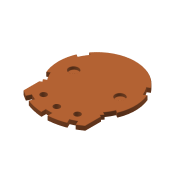
# Autodesk Inventor part: base
Saved by Autodesk Inventor 2015 SP1 (Build 190203100, 203)
## iProperties
Created: 2015-06-21
Part Number: base
Material: Generic
Document SubType Name: Modeling
Designer: Peter Mulkers
Density: 1 g/cm^3
Appearance: Orange
Author: Peter Mulkers
Autodesk Inventor part; units mm, degrees
ref_plane "YZ Plane" through (0, 0, 0) normal (1, 0, 0) x (0, 1, 0)
ref_plane "XZ Plane" through (0, 0, 0) normal (0, 1, 0) x (-1, 0, 0)
ref_plane "XY Plane" through (0, 0, 0) normal (0, 0, 1) x (1, 0, 0)
sketch "Sketch1" plane through (0, 0, 0) normal (0, 0, 1) x (1, 0, 0)
  line L0 (0, 0) -> (0, 12.5) construction
  line L1 (0, 0) -> (-10.8253, 6.25) construction
  line L2 (0, 0) -> (-10.8253, -6.25) construction
  line L3 (0, 0) -> (0, -12.5) construction
  line L4 (0, 0) -> (10.8253, -6.25) construction
  line L5 (0, 0) -> (10.8253, 6.25) construction
  line L6 (-9.9971, 7.5039) -> (-9.1242, 6.9999)
  line L7 (-11.4971, 4.9058) -> (-10.6242, 4.4018)
  line L8 (9.9971, 7.5039) -> (9.1242, 6.9999)
  line L9 (11.4971, 4.9058) -> (10.6242, 4.4018)
  arc A0 (9.9971, 7.5039) -> (-9.9971, 7.5039) centre (0, 0) ccw
  line L10 (-17.5, 0) -> (17.5, 0) construction
  line L11 (-9.9971, -7.5039) -> (-9.1242, -6.9999)
  line L12 (-11.4971, -4.9058) -> (-10.6242, -4.4018)
  line L13 (9.9971, -7.5039) -> (9.1242, -6.9999)
  line L14 (11.4971, -4.9058) -> (10.6242, -4.4018)
  arc A1 (-11.4971, 4.9058) -> (-11.4971, -4.9058) centre (0, 0) ccw
  arc A2 (11.4971, -4.9058) -> (11.4971, 4.9058) centre (0, 0) ccw
  line L15 (-10, -8.6603) -> (-10, -13.7477)
  line L16 (-9.3566, -8.2888) -> (-10, -8.6603)
  line L17 (10, -8.6603) -> (10, -13.7477)
  line L18 (9.3566, -8.2888) -> (10, -8.6603)
  arc A3 (-9.9971, -7.5039) -> (-9.3566, -8.2888) centre (0, 0) ccw
  arc A4 (9.3566, -8.2888) -> (9.9971, -7.5039) centre (0, 0) ccw
  arc A5 (-9.1242, 6.9999) -> (-10.6242, 4.4018) centre (0, 0) ccw
  arc A6 (-10.6242, -4.4018) -> (-9.1242, -6.9999) centre (0, 0) ccw
  arc A7 (9.1242, -6.9999) -> (10.6242, -4.4018) centre (0, 0) ccw
  arc A8 (10.6242, 4.4018) -> (9.1242, 6.9999) centre (0, 0) ccw
  arc A9 (-10, -8.3066) -> (10, -8.3066) centre (0, 0) ccw construction
  line L19 (0, 0) -> (-7.1845, -15.4072) construction
  line L20 (0, 0) -> (7.1845, -15.4072) construction
  circle A10 centre (-5.494, -11.782) radius 1
  circle A11 centre (0, -13) radius 1
  circle A12 centre (5.494, -11.782) radius 1
  line L21 (-7.4432, -13.5959) -> (-8.0784, -14.9579)
  line L22 (5.6306, -14.4411) -> (6.2658, -15.8032)
  line L23 (-1, -15.4677) -> (-1, -16.9706)
  line L24 (-5.6306, -14.4411) -> (-6.2658, -15.8032)
  line L25 (1, -15.4677) -> (1, -16.9706)
  line L26 (7.4432, -13.5959) -> (8.0784, -14.9579)
  arc A13 (-7.4432, -13.5959) -> (-5.6306, -14.4411) centre (0, 0) ccw
  arc A14 (-1, -15.4677) -> (1, -15.4677) centre (0, 0) ccw
  arc A15 (5.6306, -14.4411) -> (7.4432, -13.5959) centre (0, 0) ccw
  arc A16 (-10, -13.7477) -> (-8.0784, -14.9579) centre (0, 0) ccw
  arc A17 (-6.2658, -15.8032) -> (-1, -16.9706) centre (0, 0) ccw
  arc A18 (1, -16.9706) -> (6.2658, -15.8032) centre (0, 0) ccw
  arc A19 (8.0784, -14.9579) -> (10, -13.7477) centre (0, 0) ccw
  dimension "d7" = 360
  dimension "d12" = 3
  dimension "d13" = 12.5
  dimension "d14" = 10
  dimension "d16" = 1
  dimension "d19" = 11.5
  dimension "d21" = 25
  dimension "d22" = 25
  dimension "d23" = 2
  dimension "d24" = 2
  dimension "d25" = 2
  dimension "d27" = 1
  dimension "d28" = 1
  dimension "d29" = 1
  dimension "d30" = 15.5
  dimension "d31" = 15.5
  dimension "d32" = 15.5
  dimension "d33" = 17
  dimension "d34" = 13
  constraints: 52 end point, 38 point on circle, 22 symmetric about line, 20 centre point, 6 coincident, 4 parallel, 4 point on line, 3 vertical, 19 other
  measures "d12" distance between parallel lines of L7 L6
  measures "d13" radius of A0
  measures "d14" distance between parallel lines of L3 L15
  measures "d16" distance between parallel lines of L16 L11
  measures "d19" radius of A5
  measures "d21" angle of L3 L19
  measures "d22" angle of L20 L3
  measures "d23" diameter of A10
  measures "d24" diameter of A11
  measures "d25" diameter of A12
  measures "d27" distance between parallel lines of L19 L21
  measures "d28" distance between parallel lines of L3 L23
  measures "d29" distance between parallel lines of L20 L22
  measures "d30" radius of A13
  measures "d31" radius of A14
  measures "d32" radius of A15
  measures "d33" radius of A16
  measures "d34" radius of A9
extrude "Extrusion1" add sketch "Sketch1" along normal blind 1.5
sketch "Sketch2" plane through (0, 0, 1.5) normal (0, 0, 1) x (1, 0, 0)
  circle A0 centre (-7.5, 0) radius 1.5
  circle A1 centre (7.5, 0) radius 1.5
  point P0 (0, 0)
  dimension "d38" = 3
  dimension "d39" = 3
  dimension "d40" = 7.5
  dimension "d41" = 7.5
  constraints: 2 centre point, 2 horizontal alignment
  measures "d38" diameter of A0
  measures "d39" diameter of A1
  measures "d40" distance of point (0, 0) A0.centre
  measures "d41" distance of point (0, 0) A1.centre
extrude "Extrusion2" cut sketch "Sketch2" against normal blind 1
fillet "Fillet2" radius 0.125 4 edges at (-9, 0, 1.5) (-9, 0, 0.5) (6, 0, 1.5) (6, 0, 0.5)
fillet "Fillet3" radius 0.15 68 edges at (-9.5607, 7.2519, 1.5) (-9.9593, 5.75, 1.5) (-11.0607, 4.6538, 1.5) (-12.5, 0, 1.5) (-11.0607, -4.6538, 1.5) (-9.9593, -5.75, 1.5) (-9.5607, -7.2519, 1.5) (-9.6848, -7.9028, 1.5) (-9.6783, -8.4745, 1.5) (-10, -11.204, 1.5) (-9.0594, -14.385, 1.5) (-7.7608, -14.2769, 1.5) (-6.5506, -14.0478, 1.5) (-5.9482, -15.1221, 1.5) (-3.6795, -16.597, 1.5) (-1, -16.2191, 1.5) (0, -15.5, 1.5) (1, -16.2191, 1.5) (3.6795, -16.597, 1.5) (5.9482, -15.1221, 1.5) (6.5506, -14.0478, 1.5) (7.7608, -14.2769, 1.5) (9.0594, -14.385, 1.5) (10, -11.204, 1.5) (9.6783, -8.4745, 1.5) (9.6848, -7.9028, 1.5) (9.5607, -7.2519, 1.5) (9.9593, -5.75, 1.5) (11.0607, -4.6538, 1.5) (12.5, 0, 1.5) (11.0607, 4.6538, 1.5) (9.9593, 5.75, 1.5) (9.5607, 7.2519, 1.5) (0, 12.5, 1.5) (-9.5607, 7.2519, 0) (0, 12.5, 0) (9.5607, 7.2519, 0) (9.9593, 5.75, 0) (11.0607, 4.6538, 0) (12.5, 0, 0) (11.0607, -4.6538, 0) (9.9593, -5.75, 0) (9.5607, -7.2519, 0) (9.6848, -7.9028, 0) (9.6783, -8.4745, 0) (10, -11.204, 0) (9.0594, -14.385, 0) (7.7608, -14.2769, 0) (6.5506, -14.0478, 0) (5.9482, -15.1221, 0) (3.6795, -16.597, 0) (1, -16.2191, 0) (0, -15.5, 0) (-1, -16.2191, 0) (-3.6795, -16.597, 0) (-5.9482, -15.1221, 0) (-6.5506, -14.0478, 0) (-7.7608, -14.2769, 0) (-9.0594, -14.385, 0) (-10, -11.204, 0) (-9.6783, -8.4745, 0) (-9.6848, -7.9028, 0) (-9.5607, -7.2519, 0) (-9.9593, -5.75, 0) (-11.0607, -4.6538, 0) (-12.5, 0, 0) (-11.0607, 4.6538, 0) (-9.9593, 5.75, 0)
body "Solid1"
